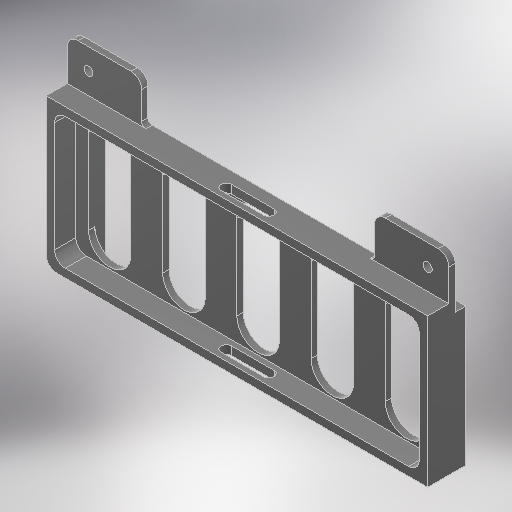
# Autodesk Inventor part: 3D_LiPo-holder
Saved by Autodesk Inventor 2025.3 (Build 293356030, 356C)
## iProperties
Created: 2026-09-02
Part Number: 3D_LiPo-holder
Material: 一般
Document SubType Name: Modeling
Designer: ibuki_ono
Density: 1 g/cm^3
Appearance: 滑らか - 黒
Author: ibuki_ono
## iProperties of the stored document 3D_LiPo-holder_3D プリント.ipt
Created: 2026-09-09
Part Number: 3D_LiPo-holder_3D プリント
Material: 一般
Document SubType Name: Modeling
Designer: ibuki_ono
Density: 1 g/cm^3
Appearance: 既定
Author: ibuki_ono
Autodesk Inventor part; units mm, degrees
ref_plane "YZ Plane" through (0, 0, 0) normal (1, 0, 0) x (0, 1, 0)
ref_plane "XZ Plane" through (0, 0, 0) normal (0, 1, 0) x (-1, 0, 0)
ref_plane "XY Plane" through (0, 0, 0) normal (0, 0, 1) x (1, 0, 0)
sketch "スケッチ1" plane through (0, 0, 0) normal (0, 0, 1) x (1, 0, 0)
  line L0 (-90, -35) -> (90, -35)
  line L1 (90, -35) -> (90, 35)
  line L2 (90, 35) -> (-90, 35)
  line L3 (-90, 35) -> (-90, -35)
  line L4 (-90, -35) -> (90, 35) construction
  line L5 (90, -35) -> (-90, 35) construction
  line L6 (-90, 35) -> (90, 35)
  line L7 (90, 35) -> (90, 55)
  line L8 (90, 55) -> (-90, 55)
  line L9 (-90, 55) -> (-90, 35)
  line L10 (-90, 55) -> (-55, 55)
  line L11 (-55, 55) -> (-55, 35)
  line L12 (-55, 35) -> (-90, 35)
  line L13 (-90, 35) -> (-90, 55)
  line L14 (90, 55) -> (55, 55)
  line L15 (55, 55) -> (55, 35)
  line L16 (55, 35) -> (90, 35)
  line L17 (90, 35) -> (90, 55)
  line L18 (-55, 35) -> (55, 35)
  line L19 (55, 35) -> (55, 40)
  line L20 (55, 40) -> (-55, 40)
  line L21 (-55, 40) -> (-55, 35)
  point P0 (0, 0)
  point P1 (55, 55)
  point P2 (-55, 40)
  point P3 (-55, 55)
  dimension "d0" = 180
  dimension "d1" = 70
  dimension "d2" = 20
  dimension "d3" = 35
  dimension "d4" = 20
  dimension "d5" = 35
  dimension "d6" = 5
  constraints: 44 end point, 10 parallel, 5 horizontal, 5 perpendicular, 2 midpoint, 2 point on line
  measures "d0" distance of L2.end L1.end
  measures "d1" distance of L1.end L0.end
  measures "d2" distance of L1.end L7.end
  measures "d3" distance of L11.end L12.end
  measures "d4" distance of L10.end L11.end
  measures "d5" distance of L16.end L15.end
  measures "d6" distance of L19.end L18.end
extrude "押し出し1" add sketch "スケッチ1" along normal blind 3 contours L3 L2 L1 L0 | L9 L8 L11 L2 | L2 L15 L8 L7
sketch "スケッチ2" plane through (0, 0, 3) normal (0, 0, 1) x (1, 0, 0)
  line L0 (-90, 55) -> (-90, -35) projected
  line L1 (-90, -35) -> (90, -35) projected
  line L2 (90, 35) -> (-90, 35)
  line L3 (-90, 35) -> (-90, -35)
  line L4 (-90, -35) -> (90, -35)
  line L5 (90, -35) -> (90, 35)
  line L6 (90, 35) -> (-90, -35) construction
  line L7 (-90, 35) -> (90, -35) construction
  line L8 (-86, 31) -> (86, 31)
  line L9 (86, 31) -> (86, -31)
  line L10 (86, -31) -> (-86, -31)
  line L11 (-86, -31) -> (-86, 31)
  point P0 (0, 0)
  point P1 (-90, 35)
  dimension "d9" = 4
  constraints: 20 end point, 4 parallel, 2 midpoint, 2 perpendicular, 1 horizontal, 3 other
  measures "d9" distance between parallel lines of L2 L8
extrude "押し出し2" add sketch "スケッチ2" along normal blind 10
fillet "フィレット1" radius 2 2 edges at (-55, 35, 1.5) (55, 35, 1.5)
sketch "スケッチ6" plane through (-90, 35, 13) normal (0, 1, 0) x (1, 0, 0)
  line L0 (80, 5) -> (100, 5) construction
  line L1 (158, 8) -> (22, 8) projected
  line L2 (80, 2.5) -> (100, 2.5)
  line L3 (100, 7.5) -> (80, 7.5)
  arc A0 (80, 7.5) -> (80, 2.5) centre (80, 5) ccw
  arc A1 (100, 2.5) -> (100, 7.5) centre (100, 5) ccw
  line L4 (90, 5) -> (110, 5) construction
  point P0 (90, 13)
  point P1 (90, 8)
  dimension "d24" = 10
  dimension "d25" = 0
  dimension "d26" = 5
  dimension "d27" = 3
  constraints: 10 end point, 4 point on circle, 4 tangent, 2 centre point, 2 midpoint, 2 parallel, 1 collinear, 1 horizontal, 1 vertical alignment
  measures "d24" distance of L4.start L0.end
  measures "d25" distance between parallel lines of L0 L4
  measures "d26" diameter of A1
  measures "d27" distance between parallel lines of L1 L0
extrude "押し出し5" cut sketch "スケッチ6" against normal through all
sketch "スケッチ7" plane through (0, 0, 3) normal (0, 0, 1) x (1, 0, 0)
  line L0 (0, 20) -> (0, -20) construction
  line L1 (-10, 20) -> (-10, -20)
  line L2 (10, -20) -> (10, 20)
  arc A0 (10, 20) -> (-10, 20) centre (0, 20) ccw
  arc A1 (-10, -20) -> (10, -20) centre (0, -20) ccw
  line L3 (0, 0) -> (40, 0) construction
  dimension "d30" = 20
  dimension "d31" = 90
  dimension "d32" = 20
  constraints: 10 end point, 4 point on circle, 4 tangent, 2 centre point, 1 horizontal, 1 midpoint, 1 parallel, 1 perpendicular, 1 vertical
  measures "d30" distance of L3.start L0.end
  measures "d31" angle of L0 L3
  measures "d32" diameter of A1
extrude "押し出し6" cut sketch "スケッチ7" against normal through all
pattern_linear "矩形状パターン1" count 5 spacing 35 along (-1, 0, 0) of "押し出し6" first direction both ways yes
sketch "スケッチ8" plane through (0, 0, 0) normal (0, 0, -1) x (-1, 0, 0)
  line L0 (-90, -35) -> (-90, 55) projected
  line L1 (90, -35) -> (-90, -35) projected
  line L2 (-80, -20) -> (-80, 20) projected
  line L3 (-90, -35) -> (-80, -35)
  line L4 (-80, -35) -> (-80, 30)
  line L5 (-80, 30) -> (-90, 30)
  line L6 (-90, 30) -> (-90, -35)
  line L7 (-90, 35) -> (90, 35) projected
  point P0 (0, 0)
  point P1 (-90, 37.5)
  point P2 (-90, 30)
  dimension "d38" = 5
  constraints: 8 end point, 2 parallel, 1 collinear, 1 horizontal, 1 perpendicular
  measures "d38" distance between parallel lines of L7 L5
extrude "押し出し7" add sketch "スケッチ8" along normal blind 5
mirror "ミラー1" about plane through (0, 0, 0) normal (1, 0, 0) of "押し出し7"
fillet "フィレット2" radius 5 5 edges at (-86, -31, 8) (-86, 31, 8) (-90, -35, 4) (86, 31, 8) (86, -31, 8)
sketch "スケッチ9" plane through (0, 0, 3) normal (0, 0, 1) x (1, 0, 0)
  line L0 (90, 35) -> (90, 55) projected
  line L1 (90, 55) -> (55, 55) projected
  line L2 (55, 55) -> (55, 37) projected
  line L3 (-55, 37) -> (-55, 55) projected
  line L4 (-55, 55) -> (-90, 55) projected
  line L5 (-90, 55) -> (-90, 35) projected
  line L6 (-90, 35) -> (-53, 35) projected
  line L7 (53, 35) -> (90, 35) projected
  arc A0 (53, 35) -> (55, 37) centre (53, 37) ccw projected
  arc A1 (-55, 37) -> (-53, 35) centre (-53, 37) ccw projected
  point P0 (0, 0)
  point P1 (-80, 45)
  point P2 (80, 45)
  dimension "d42" = 10
  dimension "d43" = 10
  dimension "d44" = 10
  dimension "d45" = 10
  measures "d42" distance from line of L5 point (-80, 45)
  measures "d43" distance from line of point (-80, 45) L4
  measures "d44" distance from line of L0 point (80, 45)
  measures "d45" distance from line of L1 point (80, 45)
hole "穴2" at (-80, 45, 3) at (80, 45, 3) direction (0, 0, -1) diameter 4.2 end through all
fillet "フィレット3" radius 5 4 edges at (-90, 55, 1.5) (-55, 55, 1.5) (55, 55, 1.5) (90, 55, 1.5)
equation "\"d2\" = d4"
equation "\"d5\" = d3"
